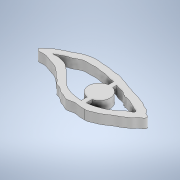
# Autodesk Inventor part: ochi
Saved by Autodesk Inventor 2022.6 (Build 266554000, 554)
## iProperties
Created: 2024-11-30
Part Number: ochi
Material: Generic
Document SubType Name: Modeling
Designer: Dragos Macovei
Density: 1 g/cm^3
Appearance: Default
Author: Dragos Macovei
Autodesk Inventor part; units mm, degrees
ref_plane "YZ Plane" through (0, 0, 0) normal (1, 0, 0) x (0, 1, 0)
ref_plane "XZ Plane" through (0, 0, 0) normal (0, 1, 0) x (-1, 0, 0)
ref_plane "XY Plane" through (0, 0, 0) normal (0, 0, 1) x (1, 0, 0)
sketch "Sketch1" plane through (0, 0, 0) normal (0, 1, 0) x (-1, 0, 0)
  line L0 (0, 0) -> (40, 0)
  line L1 (40, 0) -> (40, 40)
  line L2 (40, 40) -> (0, 40)
  line L3 (0, 40) -> (0, 0)
  line L4 (-168.0266, 205.7595) -> (174.8676, 205.7595) construction
  line L5 (174.8676, 205.7595) -> (174.8676, -251.4328) construction
  line L6 (174.8676, -251.4328) -> (-168.0266, -251.4328) construction
  line L7 (-168.0266, -251.4328) -> (-168.0266, 205.7595) construction
  spline S0 degree 5 poles (14.0954, 29.9737) (14.3687, 29.9672) (14.8839, 29.9771) (15.8594, 30.1008) (17.186, 29.3547) (18.845, 30.0249) (20.3503, 30.4778) (21.6247, 28.8017) (22.8311, 29.5935) (24.4432, 26.8969) (25.6372, 28.2701) (26.3136, 25.8889) (27.4146, 26.0432) (28.4898, 24.551) (29.1006, 24.1339) (30.254, 23.117) (31.043, 22.6519) (32.1526, 22.2252) (33.4501, 21.9175) (35.1664, 21.1882) (35.8441, 20.988) (37.7608, 21.3892) (38.2265, 20.9097) (38.7385, 19.9486) (37.037, 19.6951) (36.7385, 18.231) (34.8648, 17.8502) (33.6078, 16.5893) (31.746, 16.3528) (30.4221, 14.9744) (28.554, 14.6229) (27.4575, 14.2522) (24.7554, 14.0627) (24.2683, 14.567) (22.7428, 14.2611) (20.2568, 14.7683) (19.5537, 15.0647) (17.4049, 14.7761) (16.7758, 15.6566) (15.203, 15.6905) (14.1151, 16.3428) (13.412, 16.6841) (12.1211, 16.8793) (11.4042, 17.3195) (10.2868, 17.6705) (8.8572, 17.7868) (7.6215, 18.7525) (6.4146, 18.5061) (5.3074, 19.976) (4.3993, 19.7042) (3.3458, 20.6053) (3.0813, 21.4603) (2.2994, 21.6881) (1.3133, 21.879) (1.933, 23.0874) (2.4825, 23.1737) (3.7039, 24.0109) (3.6114, 24.8485) (4.8859, 25.0938) (5.5698, 26.0107) (6.8225, 26.583) (7.4897, 26.7912) (8.6387, 27.7109) (9.3939, 28.14) (10.2748, 28.7899) (11.1706, 29.0929) (12.3106, 29.4899) (13.1156, 30.038) (13.5547, 30.0001) (13.883, 29.9787) (14.0954, 29.9737) knots 0 0 0 0 0 0 0.020065 0.033747 0.05073 0.06781 0.085169 0.101632 0.117965 0.134009 0.15018 0.165242 0.180614 0.195494 0.210169 0.22493 0.240472 0.256005 0.272086 0.287551 0.301624 0.314687 0.32795 0.34152 0.356682 0.373583 0.391637 0.40998 0.428264 0.446676 0.463973 0.480704 0.498042 0.515047 0.531586 0.548469 0.56541 0.581172 0.596316 0.610832 0.625008 0.638784 0.652928 0.66785 0.683049 0.698869 0.714575 0.729859 0.744295 0.758037 0.770741 0.78305 0.794932 0.807265 0.819631 0.832476 0.846073 0.860213 0.874044 0.888485 0.903015 0.917178 0.931129 0.945568 0.959689 0.973405 0.984413 1 1 1 1 1 1
  spline S1 degree 5 poles (34.5557, 19.6826) (34.5737, 19.747) (34.2894, 19.7587) (32.9683, 19.4975) (32.3897, 19.7693) (31.2329, 19.9869) (30.1405, 20.2682) (29.2412, 20.8977) (28.5412, 21.5843) (27.7744, 22.1099) (27.0932, 22.8705) (26.4291, 23.4259) (25.6065, 24.4927) (24.8656, 24.8043) (23.8526, 26.1115) (22.7996, 26.7746) (21.8187, 27.1589) (20.139, 27.8283) (19.2899, 27.7281) (17.7817, 28.228) (16.0028, 27.9195) (15.1619, 27.9612) (13.4103, 27.7054) (12.2133, 27.1014) (10.6202, 26.7092) (9.6333, 25.9165) (8.3666, 25.1465) (7.362, 24.5202) (6.9099, 23.3242) (4.9083, 23.2821) (4.8831, 21.8752) (6.5322, 22.0301) (6.5957, 21.3889) (7.3599, 21.4719) (7.7598, 20.9623) (8.3895, 20.7351) (8.7794, 20.6112) (9.5472, 20.1629) (9.8909, 20.3322) (10.7592, 19.671) (11.2227, 20.4495) (11.3154, 19.2452) (11.9968, 20.0773) (12.1249, 19.0634) (12.5944, 19.1036) (12.935, 18.8151) (13.4435, 18.7794) (14.19, 18.6537) (14.7632, 18.5329) (15.5886, 18.1141) (15.7884, 17.92) (16.7643, 17.8606) (17.3174, 17.4084) (17.9522, 17.7201) (19.2374, 17.228) (19.5919, 17.0165) (21.3724, 16.5979) (22.3109, 16.8179) (23.4804, 16.3) (24.5424, 16.4154) (25.8142, 16.5657) (27.5164, 16.3223) (28.218, 16.6613) (28.939, 16.9241) (30.0003, 17.5826) (30.6077, 17.9522) (31.2092, 17.8695) (31.7976, 18.3114) (32.2762, 18.3847) (33.0817, 18.9546) (33.2182, 18.9902) (34.2383, 19.4375) (34.5384, 19.6211) (34.5557, 19.6826) knots 0 0 0 0 0 0 0.018316 0.031133 0.047102 0.063494 0.079042 0.094317 0.109224 0.124214 0.139268 0.155099 0.17146 0.18821 0.205449 0.222795 0.24015 0.257933 0.275571 0.293182 0.311429 0.329751 0.347732 0.366094 0.384059 0.40172 0.41933 0.435821 0.451898 0.466791 0.480419 0.492719 0.504923 0.516181 0.527852 0.539619 0.551724 0.563298 0.574643 0.585399 0.596083 0.606018 0.616026 0.626146 0.636924 0.648129 0.659983 0.671992 0.684524 0.696951 0.709158 0.721854 0.735309 0.749838 0.765201 0.781272 0.79739 0.814395 0.831508 0.847986 0.864099 0.880349 0.895458 0.908982 0.922116 0.934777 0.946694 0.95877 0.971799 0.982525 1 1 1 1 1 1
  circle A0 centre (16.5184, 22.771) radius 3.4667
  point P0 (17.0841, 29.7138)
  point P1 (18.8383, 29.9737)
  point P2 (20.3327, 29.9737)
  point P3 (21.6321, 29.324)
  point P4 (22.8666, 28.8692)
  point P5 (24.5559, 27.6997)
  point P6 (25.5304, 27.4398)
  point P7 (26.44, 26.4002)
  point P8 (27.4146, 25.6855)
  point P9 (28.4542, 24.7109)
  point P10 (29.2338, 23.9962)
  point P11 (30.2084, 23.2166)
  point P12 (31.0531, 22.6968)
  point P13 (32.0276, 22.307)
  point P14 (33.457, 21.8522)
  point P15 (35.0813, 21.2674)
  point P16 (36.3158, 21.1375)
  point P17 (37.7452, 21.1375)
  point P18 (38.2483, 20.7423)
  point P19 (38.3341, 20.2368)
  point P20 (37.6474, 19.6646)
  point P21 (36.628, 18.6915)
  point P22 (35.1916, 17.7648)
  point P23 (33.5235, 16.8381)
  point P24 (31.8554, 16.0967)
  point P25 (30.2337, 15.17)
  point P26 (28.6583, 14.614)
  point P27 (27.0365, 14.2896)
  point P28 (24.9978, 14.2433)
  point P29 (24.1174, 14.3823)
  point P30 (22.7737, 14.4286)
  point P31 (20.5032, 14.753)
  point P32 (19.1595, 14.9383)
  point P33 (17.5841, 15.0773)
  point P34 (16.5184, 15.4944)
  point P35 (15.1746, 15.865)
  point P36 (14.0954, 16.3284)
  point P37 (13.2749, 16.6527)
  point P38 (12.2555, 16.9308)
  point P39 (11.4214, 17.2551)
  point P40 (10.4021, 17.5795)
  point P41 (8.9657, 17.9501)
  point P42 (7.5756, 18.5062)
  point P43 (6.3709, 18.9232)
  point P44 (5.2125, 19.6646)
  point P45 (4.2858, 20)
  point P46 (3.4205, 20.7303)
  point P47 (2.8957, 21.379)
  point P48 (2.2007, 21.7033)
  point P49 (1.691, 22.074)
  point P50 (1.8763, 22.769)
  point P51 (2.525, 23.2787)
  point P52 (3.4205, 24.0201)
  point P53 (3.8687, 24.6688)
  point P54 (4.6564, 25.1785)
  point P55 (5.6758, 25.9199)
  point P56 (6.7415, 26.5222)
  point P57 (7.5756, 26.9393)
  point P58 (8.595, 27.6343)
  point P59 (9.429, 28.1903)
  point P60 (10.2631, 28.7)
  point P61 (11.2361, 29.117)
  point P62 (12.4408, 29.6267)
  point P63 (13.3675, 29.9737)
  point P64 (32.3414, 19.7408)
  point P65 (31.2633, 20)
  point P66 (30.127, 20.3818)
  point P67 (29.2238, 20.9645)
  point P68 (28.4954, 21.5764)
  point P69 (27.7962, 22.1591)
  point P70 (27.1261, 22.8001)
  point P71 (26.4559, 23.4702)
  point P72 (25.6693, 24.286)
  point P73 (24.9118, 24.927)
  point P74 (23.8629, 25.9467)
  point P75 (22.814, 26.7043)
  point P76 (21.7068, 27.1996)
  point P77 (20.2792, 27.6658)
  point P78 (19.2303, 27.8406)
  point P79 (17.7735, 28.0445)
  point P80 (16.1419, 27.9862)
  point P81 (15.0348, 27.8988)
  point P82 (13.578, 27.6366)
  point P83 (12.1212, 27.1413)
  point P84 (10.6935, 26.5877)
  point P85 (9.5281, 25.8885)
  point P86 (8.3627, 25.1309)
  point P87 (7.4595, 24.3734)
  point P88 (6.4689, 23.5285)
  point P89 (5.1869, 22.771)
  point P90 (5.3617, 22.1591)
  point P91 (6.3815, 21.7803)
  point P92 (6.7894, 21.5181)
  point P93 (7.2847, 21.3433)
  point P94 (7.8091, 21.0228)
  point P95 (8.3335, 20.7606)
  point P96 (8.8289, 20.5566)
  point P97 (9.4698, 20.2944)
  point P98 (10.0234, 20.1487)
  point P99 (10.8101, 20)
  point P100 (11.1597, 20)
  point P101 (11.4511, 19.6826)
  point P102 (11.859, 19.6826)
  point P103 (12.2086, 19.2747)
  point P104 (12.5582, 19.0416)
  point P105 (12.9078, 18.8959)
  point P106 (13.374, 18.7794)
  point P107 (14.0954, 18.6628)
  point P108 (14.8308, 18.4589)
  point P109 (15.5009, 18.1384)
  point P110 (15.9088, 17.9636)
  point P111 (16.6372, 17.7888)
  point P112 (17.2782, 17.5848)
  point P113 (17.9192, 17.5557)
  point P114 (18.9389, 17.3226)
  point P115 (19.7256, 17.0312)
  point P116 (21.1824, 16.7399)
  point P117 (22.3769, 16.6525)
  point P118 (23.4258, 16.4485)
  point P119 (24.5039, 16.4194)
  point P120 (25.9606, 16.4777)
  point P121 (27.534, 16.4777)
  point P122 (28.2915, 16.6816)
  point P123 (29.049, 17.0312)
  point P124 (30.0688, 17.6139)
  point P125 (30.7098, 17.8762)
  point P126 (31.2342, 17.9927)
  point P127 (31.7586, 18.2258)
  point P128 (32.2831, 18.4589)
  point P129 (32.8949, 18.8085)
  point P130 (33.5942, 19.1581)
  dimension "d0" = 40
  dimension "d1" = 40
  constraints: 8 end point, 2 parallel, 1 centre point, 1 horizontal, 1 perpendicular, 137 other
  measures "d0" distance of L2.end L1.end
  measures "d1" distance of L1.end L0.end
extrude "Extrusion1" add sketch "Sketch1" along normal blind 3 contours S0 | A0
sketch "Sketch2" plane through (-16.5184, 3, 22.771) normal (0, 1, 0) x (1, 0, 0)
  line L0 (-0.5129, 2.4043) -> (0.9695, 2.4043)
  line L1 (0.9695, 2.4043) -> (0.9695, 6.7525)
  line L2 (0.9695, 6.7525) -> (-0.5129, 6.7525)
  line L3 (-0.5129, 6.7525) -> (-0.5129, 2.4043)
  line L4 (-0.5129, -6.391) -> (0.9695, -6.391)
  line L5 (0.9695, -6.391) -> (0.9695, -1.6475)
  line L6 (0.9695, -1.6475) -> (-0.5129, -1.6475)
  line L7 (-0.5129, -1.6475) -> (-0.5129, -6.391)
  point P0 (16.5184, 22.771)
  constraints: 16 end point, 4 parallel, 2 horizontal, 2 perpendicular, 2 point on line
extrude "Extrusion2" add sketch "Sketch2" against normal blind 1
body "Solid1"
